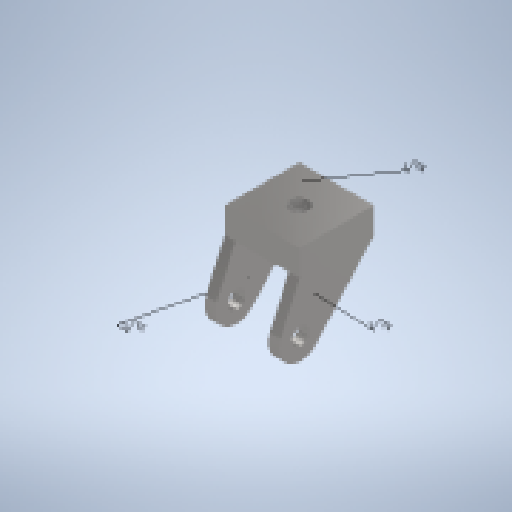
# Autodesk Inventor part: Beugel
Saved by Autodesk Inventor 2023.2 (Build 272271000, 271)
## iProperties
Created: 2023-06-25
Part Number: Beugel
Material: Steel, Mild
Document SubType Name: Modeling
Designer: Jeroen
Density: 7.85 g/cm^3
Appearance: Semi-Polished
Author: Jeroen
Autodesk Inventor part; units mm, degrees
ref_plane "YZ Plane" through (0, 0, 0) normal (1, 0, 0) x (0, 1, 0)
ref_plane "XZ Plane" through (0, 0, 0) normal (0, 1, 0) x (-1, 0, 0)
ref_plane "XY Plane" through (0, 0, 0) normal (0, 0, 1) x (1, 0, 0)
sketch "Sketch1" plane through (0, 0, 0) normal (1, 0, 0) x (0, 1, 0)
  line L0 (14.0617, -50.4204) -> (14.0617, -15.4204)
  line L1 (14.0617, -15.4204) -> (2.0617, -15.4204)
  line L2 (2.0617, -15.4204) -> (-17.9628, -6.7446)
  arc A0 (-17.9628, -6.7446) -> (-28.5528, -23.4204) centre (-21.9383, -15.9204) ccw
  line L3 (-28.5528, -23.4204) -> (2.0617, -50.4204)
  line L4 (2.0617, -50.4204) -> (14.0617, -50.4204)
  line L5 (2.0617, -15.4204) -> (2.0617, -50.4204) construction
  circle A1 centre (-21.9383, -15.9204) radius 4
  point P0 (0, 0)
  point P1 (14.0617, -32.9204)
  dimension "d0" = 12
  dimension "d1" = 17
  dimension "d2" = 36
  dimension "d3" = 10
  dimension "d43" = 8
  constraints: 12 end point, 2 centre point, 2 coincident, 2 perpendicular, 2 point on circle, 2 tangent, 1 horizontal, 1 midpoint, 1 vertical, 2 other
  measures "d0" distance of L3.end L0.start
  measures "d1" vertical distance of A0.centre point (14.062, -32.92)
  measures "d2" horizontal distance of point (14.062, -32.92) A0.centre
  measures "d3" radius of A0
  measures "d43" diameter of A1
extrude "Extrusion1" add sketch "Sketch1" along normal mid plane 35
sketch "Sketch2" plane through (17.5, 14.0617, -50.4204) normal (0, 0, -1) x (-1, 0, 0)
  line L0 (35, -12) -> (0, -12) projected
  line L1 (30, -12) -> (30, -46)
  line L2 (30, -46) -> (5, -46)
  line L3 (5, -46) -> (5, -12)
  line L4 (35, -46) -> (0, -46) projected
  line L5 (35, -12) -> (0, -12) projected
  point P0 (17.5, -14.0617)
  point P1 (17.5, -46)
  dimension "d6" = 25
  constraints: 6 end point, 2 midpoint, 2 point on line, 1 collinear, 1 parallel, 1 perpendicular, 1 vertical
  measures "d6" distance of L1.end L2.end
extrude "Extrusion2" cut sketch "Sketch2" against normal through all
sketch "Sketch3" plane through (-17.5, 14.0617, -15.4204) normal (0, 1, 0) x (1, 0, 0)
  line L0 (35, 0) -> (0, 0) construction
  line L1 (0, 35) -> (0, 7.9999) construction
  line L2 (35, 0) -> (0, 35) construction
  point P0 (17.5, -15.4204)
  point P1 (17.5, 17.5)
  constraints: 2 end point, 1 midpoint
hole "Hole1" at (0, 14.0617, -32.9204) direction (0, -1, 0) diameter 8.376 depth 12 thread size "M10x1.5" class "6H" standard "ISO Metric profile"
body "Solid1"
